Autodesk Fusion 360 part; units mm, degrees
(part 3 of 3)
extrude "Upper ledge pad 189" add sketch "Upper ledge pad 189 outline" along normal blind 2.5 separate body makes body 24 in component "REFERENCE - v11 rubber contact pads"
ref_plane "WorkPlane6" through (0, 0, -2.5) normal (0, 0, 1) x (1, 0, 0) in component "REFERENCE - v11 rubber contact pads"
sketch "Moving shoe rubber pad 189 outline" plane through (0, 0, -2.5) normal (0, 0, 1) x (1, 0, 0) in component "REFERENCE - v11 rubber contact pads"
  line L0 (181, 9.5) -> (197, 9.5)
  line L1 (199, 11.5) -> (199, 23.5)
  line L2 (197, 25.5) -> (181, 25.5)
  line L3 (179, 23.5) -> (179, 11.5)
  arc A0 (197, 9.5) -> (199, 11.5) centre (197, 11.5) ccw
  arc A1 (199, 23.5) -> (197, 25.5) centre (197, 23.5) ccw
  arc A2 (181, 25.5) -> (179, 23.5) centre (181, 23.5) ccw
  arc A3 (179, 11.5) -> (181, 9.5) centre (181, 11.5) ccw
extrude "Moving shoe rubber pad 189" add sketch "Moving shoe rubber pad 189 outline" along normal blind 2.5 separate body makes body 25 in component "REFERENCE - v11 rubber contact pads"
ref_plane "WorkPlane1" through (0, 0, -40) normal (0, 0, 1) x (1, 0, 0) in component "REFERENCE - M5 x 30 DIN 933 clamp bolts"
sketch "M5 hex head 25 outline" plane through (0, 0, -40) normal (0, 0, 1) x (1, 0, 0) in component "REFERENCE - M5 x 30 DIN 933 clamp bolts"
  line L0 (29.6188, 17.5) -> (27.3094, 21.5)
  line L1 (27.3094, 21.5) -> (22.6906, 21.5)
  line L2 (22.6906, 21.5) -> (20.3812, 17.5)
  line L3 (20.3812, 17.5) -> (22.6906, 13.5)
  line L4 (22.6906, 13.5) -> (27.3094, 13.5)
  line L5 (27.3094, 13.5) -> (29.6188, 17.5)
extrude "M5 hex head 25" add sketch "M5 hex head 25 outline" along normal blind 3.5 separate body makes body 26 in component "REFERENCE - M5 x 30 DIN 933 clamp bolts"
ref_plane "WorkPlane2" through (0, 0, -36.5) normal (0, 0, 1) x (1, 0, 0) in component "REFERENCE - M5 x 30 DIN 933 clamp bolts"
sketch "M5 full-thread envelope 25 layout" plane through (0, 0, -36.5) normal (0, 0, 1) x (1, 0, 0) in component "REFERENCE - M5 x 30 DIN 933 clamp bolts"
  circle A0 centre (25, 17.5) radius 2.5
extrude "M5 full-thread envelope 25" add sketch "M5 full-thread envelope 25 layout" along normal blind 30 bodies 26 in component "REFERENCE - M5 x 30 DIN 933 clamp bolts"
ref_plane "WorkPlane1" through (0, 0, -23.7) normal (0, 0, 1) x (1, 0, 0) in component "REFERENCE - M5 DIN 934 captive nuts"
sketch "M5 nut 25 outline" plane through (0, 0, -23.7) normal (0, 0, 1) x (1, 0, 0) in component "REFERENCE - M5 DIN 934 captive nuts"
  line L0 (29.6188, 17.5) -> (27.3094, 21.5)
  line L1 (27.3094, 21.5) -> (22.6906, 21.5)
  line L2 (22.6906, 21.5) -> (20.3812, 17.5)
  line L3 (20.3812, 17.5) -> (22.6906, 13.5)
  line L4 (22.6906, 13.5) -> (27.3094, 13.5)
  line L5 (27.3094, 13.5) -> (29.6188, 17.5)
extrude "M5 nut 25" add sketch "M5 nut 25 outline" along normal blind 4 separate body makes body 27 in component "REFERENCE - M5 DIN 934 captive nuts"
ref_plane "WorkPlane2" through (0, 0, -23.8) normal (0, 0, 1) x (1, 0, 0) in component "REFERENCE - M5 DIN 934 captive nuts"
sketch "M5 thread clearance envelope 25 layout" plane through (0, 0, -23.8) normal (0, 0, 1) x (1, 0, 0) in component "REFERENCE - M5 DIN 934 captive nuts"
  circle A0 centre (25, 17.5) radius 2.6
extrude "M5 thread clearance envelope 25" cut sketch "M5 thread clearance envelope 25 layout" along normal blind 4.2 bodies 27 in component "REFERENCE - M5 DIN 934 captive nuts"
ref_plane "WorkPlane3" through (0, 0, -40) normal (0, 0, 1) x (1, 0, 0) in component "REFERENCE - M5 x 30 DIN 933 clamp bolts"
sketch "M5 hex head 189 outline" plane through (0, 0, -40) normal (0, 0, 1) x (1, 0, 0) in component "REFERENCE - M5 x 30 DIN 933 clamp bolts"
  line L0 (193.6188, 17.5) -> (191.3094, 21.5)
  line L1 (191.3094, 21.5) -> (186.6906, 21.5)
  line L2 (186.6906, 21.5) -> (184.3812, 17.5)
  line L3 (184.3812, 17.5) -> (186.6906, 13.5)
  line L4 (186.6906, 13.5) -> (191.3094, 13.5)
  line L5 (191.3094, 13.5) -> (193.6188, 17.5)
extrude "M5 hex head 189" add sketch "M5 hex head 189 outline" along normal blind 3.5 separate body makes body 28 in component "REFERENCE - M5 x 30 DIN 933 clamp bolts"
ref_plane "WorkPlane4" through (0, 0, -36.5) normal (0, 0, 1) x (1, 0, 0) in component "REFERENCE - M5 x 30 DIN 933 clamp bolts"
sketch "M5 full-thread envelope 189 layout" plane through (0, 0, -36.5) normal (0, 0, 1) x (1, 0, 0) in component "REFERENCE - M5 x 30 DIN 933 clamp bolts"
  circle A0 centre (189, 17.5) radius 2.5
extrude "M5 full-thread envelope 189" add sketch "M5 full-thread envelope 189 layout" along normal blind 30 bodies 28 in component "REFERENCE - M5 x 30 DIN 933 clamp bolts"
ref_plane "WorkPlane3" through (0, 0, -23.7) normal (0, 0, 1) x (1, 0, 0) in component "REFERENCE - M5 DIN 934 captive nuts"
sketch "M5 nut 189 outline" plane through (0, 0, -23.7) normal (0, 0, 1) x (1, 0, 0) in component "REFERENCE - M5 DIN 934 captive nuts"
  line L0 (193.6188, 17.5) -> (191.3094, 21.5)
  line L1 (191.3094, 21.5) -> (186.6906, 21.5)
  line L2 (186.6906, 21.5) -> (184.3812, 17.5)
  line L3 (184.3812, 17.5) -> (186.6906, 13.5)
  line L4 (186.6906, 13.5) -> (191.3094, 13.5)
  line L5 (191.3094, 13.5) -> (193.6188, 17.5)
extrude "M5 nut 189" add sketch "M5 nut 189 outline" along normal blind 4 separate body makes body 29 in component "REFERENCE - M5 DIN 934 captive nuts"
ref_plane "WorkPlane4" through (0, 0, -23.8) normal (0, 0, 1) x (1, 0, 0) in component "REFERENCE - M5 DIN 934 captive nuts"
sketch "M5 thread clearance envelope 189 layout" plane through (0, 0, -23.8) normal (0, 0, 1) x (1, 0, 0) in component "REFERENCE - M5 DIN 934 captive nuts"
  circle A0 centre (189, 17.5) radius 2.6
extrude "M5 thread clearance envelope 189" cut sketch "M5 thread clearance envelope 189 layout" along normal blind 4.2 bodies 27 29 in component "REFERENCE - M5 DIN 934 captive nuts"
ref_plane "WorkPlane1" through (0, 0, 80.4) normal (0, 0, 1) x (1, 0, 0) in component "REFERENCE - six M3 x 10 button screws and washers"
sketch "M3 button head envelope (18, 16) layout" plane through (0, 0, 80.4) normal (0, 0, 1) x (1, 0, 0) in component "REFERENCE - six M3 x 10 button screws and washers"
  circle A0 centre (18, 16) radius 2.85
extrude "M3 button head envelope (18, 16)" add sketch "M3 button head envelope (18, 16) layout" along normal blind 1.65 separate body makes body 30 in component "REFERENCE - six M3 x 10 button screws and washers"
ref_plane "WorkPlane2" through (0, 0, 70.4) normal (0, 0, 1) x (1, 0, 0) in component "REFERENCE - six M3 x 10 button screws and washers"
sketch "M3 screw shaft (18, 16) layout" plane through (0, 0, 70.4) normal (0, 0, 1) x (1, 0, 0) in component "REFERENCE - six M3 x 10 button screws and washers"
  circle A0 centre (18, 16) radius 1.5
extrude "M3 screw shaft (18, 16)" add sketch "M3 screw shaft (18, 16) layout" along normal blind 10 bodies 30 in component "REFERENCE - six M3 x 10 button screws and washers"
ref_plane "WorkPlane3" through (0, 0, 79.9) normal (0, 0, 1) x (1, 0, 0) in component "REFERENCE - six M3 x 10 button screws and washers"
sketch "M3 washer OD (18, 16) layout" plane through (0, 0, 79.9) normal (0, 0, 1) x (1, 0, 0) in component "REFERENCE - six M3 x 10 button screws and washers"
  circle A0 centre (18, 16) radius 3.5
extrude "M3 washer OD (18, 16)" add sketch "M3 washer OD (18, 16) layout" along normal blind 0.5 bodies 30 in component "REFERENCE - six M3 x 10 button screws and washers"
ref_plane "WorkPlane1" through (0, 0, 71.1) normal (0, 0, 1) x (1, 0, 0) in component "REFERENCE - six M3 DIN 934 nuts"
sketch "M3 nut (18, 16) outline" plane through (0, 0, 71.1) normal (0, 0, 1) x (1, 0, 0) in component "REFERENCE - six M3 DIN 934 nuts"
  line L0 (21.1754, 16) -> (19.5877, 18.75)
  line L1 (19.5877, 18.75) -> (16.4123, 18.75)
  line L2 (16.4123, 18.75) -> (14.8246, 16)
  line L3 (14.8246, 16) -> (16.4123, 13.25)
  line L4 (16.4123, 13.25) -> (19.5877, 13.25)
  line L5 (19.5877, 13.25) -> (21.1754, 16)
extrude "M3 nut (18, 16)" add sketch "M3 nut (18, 16) outline" along normal blind 2.4 separate body makes body 31 in component "REFERENCE - six M3 DIN 934 nuts"
ref_plane "WorkPlane2" through (0, 0, 71) normal (0, 0, 1) x (1, 0, 0) in component "REFERENCE - six M3 DIN 934 nuts"
sketch "M3 thread clearance envelope (18, 16) layout" plane through (0, 0, 71) normal (0, 0, 1) x (1, 0, 0) in component "REFERENCE - six M3 DIN 934 nuts"
  circle A0 centre (18, 16) radius 1.6
extrude "M3 thread clearance envelope (18, 16)" cut sketch "M3 thread clearance envelope (18, 16) layout" along normal blind 2.6 bodies 31 in component "REFERENCE - six M3 DIN 934 nuts"
ref_plane "WorkPlane4" through (0, 0, 80.4) normal (0, 0, 1) x (1, 0, 0) in component "REFERENCE - six M3 x 10 button screws and washers"
sketch "M3 button head envelope (32, 16) layout" plane through (0, 0, 80.4) normal (0, 0, 1) x (1, 0, 0) in component "REFERENCE - six M3 x 10 button screws and washers"
  circle A0 centre (32, 16) radius 2.85
extrude "M3 button head envelope (32, 16)" add sketch "M3 button head envelope (32, 16) layout" along normal blind 1.65 separate body makes body 32 in component "REFERENCE - six M3 x 10 button screws and washers"
ref_plane "WorkPlane5" through (0, 0, 70.4) normal (0, 0, 1) x (1, 0, 0) in component "REFERENCE - six M3 x 10 button screws and washers"
sketch "M3 screw shaft (32, 16) layout" plane through (0, 0, 70.4) normal (0, 0, 1) x (1, 0, 0) in component "REFERENCE - six M3 x 10 button screws and washers"
  circle A0 centre (32, 16) radius 1.5
extrude "M3 screw shaft (32, 16)" add sketch "M3 screw shaft (32, 16) layout" along normal blind 10 bodies 32 in component "REFERENCE - six M3 x 10 button screws and washers"
ref_plane "WorkPlane6" through (0, 0, 79.9) normal (0, 0, 1) x (1, 0, 0) in component "REFERENCE - six M3 x 10 button screws and washers"
sketch "M3 washer OD (32, 16) layout" plane through (0, 0, 79.9) normal (0, 0, 1) x (1, 0, 0) in component "REFERENCE - six M3 x 10 button screws and washers"
  circle A0 centre (32, 16) radius 3.5
extrude "M3 washer OD (32, 16)" add sketch "M3 washer OD (32, 16) layout" along normal blind 0.5 bodies 32 in component "REFERENCE - six M3 x 10 button screws and washers"
ref_plane "WorkPlane3" through (0, 0, 71.1) normal (0, 0, 1) x (1, 0, 0) in component "REFERENCE - six M3 DIN 934 nuts"
sketch "M3 nut (32, 16) outline" plane through (0, 0, 71.1) normal (0, 0, 1) x (1, 0, 0) in component "REFERENCE - six M3 DIN 934 nuts"
  line L0 (35.1754, 16) -> (33.5877, 18.75)
  line L1 (33.5877, 18.75) -> (30.4123, 18.75)
  line L2 (30.4123, 18.75) -> (28.8246, 16)
  line L3 (28.8246, 16) -> (30.4123, 13.25)
  line L4 (30.4123, 13.25) -> (33.5877, 13.25)
  line L5 (33.5877, 13.25) -> (35.1754, 16)
extrude "M3 nut (32, 16)" add sketch "M3 nut (32, 16) outline" along normal blind 2.4 separate body makes body 33 in component "REFERENCE - six M3 DIN 934 nuts"
ref_plane "WorkPlane4" through (0, 0, 71) normal (0, 0, 1) x (1, 0, 0) in component "REFERENCE - six M3 DIN 934 nuts"
sketch "M3 thread clearance envelope (32, 16) layout" plane through (0, 0, 71) normal (0, 0, 1) x (1, 0, 0) in component "REFERENCE - six M3 DIN 934 nuts"
  circle A0 centre (32, 16) radius 1.6
extrude "M3 thread clearance envelope (32, 16)" cut sketch "M3 thread clearance envelope (32, 16) layout" along normal blind 2.6 bodies 31 33 in component "REFERENCE - six M3 DIN 934 nuts"
ref_plane "WorkPlane7" through (0, 0, 80.4) normal (0, 0, 1) x (1, 0, 0) in component "REFERENCE - six M3 x 10 button screws and washers"
sketch "M3 button head envelope (182, 16) layout" plane through (0, 0, 80.4) normal (0, 0, 1) x (1, 0, 0) in component "REFERENCE - six M3 x 10 button screws and washers"
  circle A0 centre (182, 16) radius 2.85
extrude "M3 button head envelope (182, 16)" add sketch "M3 button head envelope (182, 16) layout" along normal blind 1.65 separate body makes body 34 in component "REFERENCE - six M3 x 10 button screws and washers"
ref_plane "WorkPlane8" through (0, 0, 70.4) normal (0, 0, 1) x (1, 0, 0) in component "REFERENCE - six M3 x 10 button screws and washers"
sketch "M3 screw shaft (182, 16) layout" plane through (0, 0, 70.4) normal (0, 0, 1) x (1, 0, 0) in component "REFERENCE - six M3 x 10 button screws and washers"
  circle A0 centre (182, 16) radius 1.5
extrude "M3 screw shaft (182, 16)" add sketch "M3 screw shaft (182, 16) layout" along normal blind 10 bodies 34 in component "REFERENCE - six M3 x 10 button screws and washers"
ref_plane "WorkPlane9" through (0, 0, 79.9) normal (0, 0, 1) x (1, 0, 0) in component "REFERENCE - six M3 x 10 button screws and washers"
sketch "M3 washer OD (182, 16) layout" plane through (0, 0, 79.9) normal (0, 0, 1) x (1, 0, 0) in component "REFERENCE - six M3 x 10 button screws and washers"
  circle A0 centre (182, 16) radius 3.5
extrude "M3 washer OD (182, 16)" add sketch "M3 washer OD (182, 16) layout" along normal blind 0.5 bodies 34 in component "REFERENCE - six M3 x 10 button screws and washers"
ref_plane "WorkPlane5" through (0, 0, 71.1) normal (0, 0, 1) x (1, 0, 0) in component "REFERENCE - six M3 DIN 934 nuts"
sketch "M3 nut (182, 16) outline" plane through (0, 0, 71.1) normal (0, 0, 1) x (1, 0, 0) in component "REFERENCE - six M3 DIN 934 nuts"
  line L0 (185.1754, 16) -> (183.5877, 18.75)
  line L1 (183.5877, 18.75) -> (180.4123, 18.75)
  line L2 (180.4123, 18.75) -> (178.8246, 16)
  line L3 (178.8246, 16) -> (180.4123, 13.25)
  line L4 (180.4123, 13.25) -> (183.5877, 13.25)
  line L5 (183.5877, 13.25) -> (185.1754, 16)
extrude "M3 nut (182, 16)" add sketch "M3 nut (182, 16) outline" along normal blind 2.4 separate body makes body 35 in component "REFERENCE - six M3 DIN 934 nuts"
ref_plane "WorkPlane6" through (0, 0, 71) normal (0, 0, 1) x (1, 0, 0) in component "REFERENCE - six M3 DIN 934 nuts"
sketch "M3 thread clearance envelope (182, 16) layout" plane through (0, 0, 71) normal (0, 0, 1) x (1, 0, 0) in component "REFERENCE - six M3 DIN 934 nuts"
  circle A0 centre (182, 16) radius 1.6
extrude "M3 thread clearance envelope (182, 16)" cut sketch "M3 thread clearance envelope (182, 16) layout" along normal blind 2.6 bodies 31 33 35 in component "REFERENCE - six M3 DIN 934 nuts"
ref_plane "WorkPlane10" through (0, 0, 80.4) normal (0, 0, 1) x (1, 0, 0) in component "REFERENCE - six M3 x 10 button screws and washers"
sketch "M3 button head envelope (196, 16) layout" plane through (0, 0, 80.4) normal (0, 0, 1) x (1, 0, 0) in component "REFERENCE - six M3 x 10 button screws and washers"
  circle A0 centre (196, 16) radius 2.85
extrude "M3 button head envelope (196, 16)" add sketch "M3 button head envelope (196, 16) layout" along normal blind 1.65 separate body makes body 36 in component "REFERENCE - six M3 x 10 button screws and washers"
ref_plane "WorkPlane11" through (0, 0, 70.4) normal (0, 0, 1) x (1, 0, 0) in component "REFERENCE - six M3 x 10 button screws and washers"
sketch "M3 screw shaft (196, 16) layout" plane through (0, 0, 70.4) normal (0, 0, 1) x (1, 0, 0) in component "REFERENCE - six M3 x 10 button screws and washers"
  circle A0 centre (196, 16) radius 1.5
extrude "M3 screw shaft (196, 16)" add sketch "M3 screw shaft (196, 16) layout" along normal blind 10 bodies 36 in component "REFERENCE - six M3 x 10 button screws and washers"
ref_plane "WorkPlane12" through (0, 0, 79.9) normal (0, 0, 1) x (1, 0, 0) in component "REFERENCE - six M3 x 10 button screws and washers"
sketch "M3 washer OD (196, 16) layout" plane through (0, 0, 79.9) normal (0, 0, 1) x (1, 0, 0) in component "REFERENCE - six M3 x 10 button screws and washers"
  circle A0 centre (196, 16) radius 3.5
extrude "M3 washer OD (196, 16)" add sketch "M3 washer OD (196, 16) layout" along normal blind 0.5 bodies 36 in component "REFERENCE - six M3 x 10 button screws and washers"
ref_plane "WorkPlane7" through (0, 0, 71.1) normal (0, 0, 1) x (1, 0, 0) in component "REFERENCE - six M3 DIN 934 nuts"
sketch "M3 nut (196, 16) outline" plane through (0, 0, 71.1) normal (0, 0, 1) x (1, 0, 0) in component "REFERENCE - six M3 DIN 934 nuts"
  line L0 (199.1754, 16) -> (197.5877, 18.75)
  line L1 (197.5877, 18.75) -> (194.4123, 18.75)
  line L2 (194.4123, 18.75) -> (192.8246, 16)
  line L3 (192.8246, 16) -> (194.4123, 13.25)
  line L4 (194.4123, 13.25) -> (197.5877, 13.25)
  line L5 (197.5877, 13.25) -> (199.1754, 16)
extrude "M3 nut (196, 16)" add sketch "M3 nut (196, 16) outline" along normal blind 2.4 separate body makes body 37 in component "REFERENCE - six M3 DIN 934 nuts"
ref_plane "WorkPlane8" through (0, 0, 71) normal (0, 0, 1) x (1, 0, 0) in component "REFERENCE - six M3 DIN 934 nuts"
sketch "M3 thread clearance envelope (196, 16) layout" plane through (0, 0, 71) normal (0, 0, 1) x (1, 0, 0) in component "REFERENCE - six M3 DIN 934 nuts"
  circle A0 centre (196, 16) radius 1.6
extrude "M3 thread clearance envelope (196, 16)" cut sketch "M3 thread clearance envelope (196, 16) layout" along normal blind 2.6 bodies 31 33 35 37 in component "REFERENCE - six M3 DIN 934 nuts"
ref_plane "WorkPlane13" through (0, 0, 80.4) normal (0, 0, 1) x (1, 0, 0) in component "REFERENCE - six M3 x 10 button screws and washers"
sketch "M3 button head envelope (92, -2.5) layout" plane through (0, 0, 80.4) normal (0, 0, 1) x (1, 0, 0) in component "REFERENCE - six M3 x 10 button screws and washers"
  circle A0 centre (92, -2.5) radius 2.85
extrude "M3 button head envelope (92, -2.5)" add sketch "M3 button head envelope (92, -2.5) layout" along normal blind 1.65 separate body makes body 38 in component "REFERENCE - six M3 x 10 button screws and washers"
ref_plane "WorkPlane14" through (0, 0, 70.4) normal (0, 0, 1) x (1, 0, 0) in component "REFERENCE - six M3 x 10 button screws and washers"
sketch "M3 screw shaft (92, -2.5) layout" plane through (0, 0, 70.4) normal (0, 0, 1) x (1, 0, 0) in component "REFERENCE - six M3 x 10 button screws and washers"
  circle A0 centre (92, -2.5) radius 1.5
extrude "M3 screw shaft (92, -2.5)" add sketch "M3 screw shaft (92, -2.5) layout" along normal blind 10 bodies 38 in component "REFERENCE - six M3 x 10 button screws and washers"
ref_plane "WorkPlane15" through (0, 0, 79.9) normal (0, 0, 1) x (1, 0, 0) in component "REFERENCE - six M3 x 10 button screws and washers"
sketch "M3 washer OD (92, -2.5) layout" plane through (0, 0, 79.9) normal (0, 0, 1) x (1, 0, 0) in component "REFERENCE - six M3 x 10 button screws and washers"
  circle A0 centre (92, -2.5) radius 3.5
extrude "M3 washer OD (92, -2.5)" add sketch "M3 washer OD (92, -2.5) layout" along normal blind 0.5 bodies 38 in component "REFERENCE - six M3 x 10 button screws and washers"
ref_plane "WorkPlane9" through (0, 0, 71.1) normal (0, 0, 1) x (1, 0, 0) in component "REFERENCE - six M3 DIN 934 nuts"
sketch "M3 nut (92, -2.5) outline" plane through (0, 0, 71.1) normal (0, 0, 1) x (1, 0, 0) in component "REFERENCE - six M3 DIN 934 nuts"
  line L0 (95.1754, -2.5) -> (93.5877, 0.25)
  line L1 (93.5877, 0.25) -> (90.4123, 0.25)
  line L2 (90.4123, 0.25) -> (88.8246, -2.5)
  line L3 (88.8246, -2.5) -> (90.4123, -5.25)
  line L4 (90.4123, -5.25) -> (93.5877, -5.25)
  line L5 (93.5877, -5.25) -> (95.1754, -2.5)
extrude "M3 nut (92, -2.5)" add sketch "M3 nut (92, -2.5) outline" along normal blind 2.4 separate body makes body 39 in component "REFERENCE - six M3 DIN 934 nuts"
ref_plane "WorkPlane10" through (0, 0, 71) normal (0, 0, 1) x (1, 0, 0) in component "REFERENCE - six M3 DIN 934 nuts"
sketch "M3 thread clearance envelope (92, -2.5) layout" plane through (0, 0, 71) normal (0, 0, 1) x (1, 0, 0) in component "REFERENCE - six M3 DIN 934 nuts"
  circle A0 centre (92, -2.5) radius 1.6
extrude "M3 thread clearance envelope (92, -2.5)" cut sketch "M3 thread clearance envelope (92, -2.5) layout" along normal blind 2.6 bodies 31 33 35 37 39 in component "REFERENCE - six M3 DIN 934 nuts"
ref_plane "WorkPlane16" through (0, 0, 80.4) normal (0, 0, 1) x (1, 0, 0) in component "REFERENCE - six M3 x 10 button screws and washers"
sketch "M3 button head envelope (122, -2.5) layout" plane through (0, 0, 80.4) normal (0, 0, 1) x (1, 0, 0) in component "REFERENCE - six M3 x 10 button screws and washers"
  circle A0 centre (122, -2.5) radius 2.85
extrude "M3 button head envelope (122, -2.5)" add sketch "M3 button head envelope (122, -2.5) layout" along normal blind 1.65 separate body makes body 40 in component "REFERENCE - six M3 x 10 button screws and washers"
ref_plane "WorkPlane17" through (0, 0, 70.4) normal (0, 0, 1) x (1, 0, 0) in component "REFERENCE - six M3 x 10 button screws and washers"
sketch "M3 screw shaft (122, -2.5) layout" plane through (0, 0, 70.4) normal (0, 0, 1) x (1, 0, 0) in component "REFERENCE - six M3 x 10 button screws and washers"
  circle A0 centre (122, -2.5) radius 1.5
extrude "M3 screw shaft (122, -2.5)" add sketch "M3 screw shaft (122, -2.5) layout" along normal blind 10 bodies 40 in component "REFERENCE - six M3 x 10 button screws and washers"
ref_plane "WorkPlane18" through (0, 0, 79.9) normal (0, 0, 1) x (1, 0, 0) in component "REFERENCE - six M3 x 10 button screws and washers"
sketch "M3 washer OD (122, -2.5) layout" plane through (0, 0, 79.9) normal (0, 0, 1) x (1, 0, 0) in component "REFERENCE - six M3 x 10 button screws and washers"
  circle A0 centre (122, -2.5) radius 3.5
extrude "M3 washer OD (122, -2.5)" add sketch "M3 washer OD (122, -2.5) layout" along normal blind 0.5 bodies 40 in component "REFERENCE - six M3 x 10 button screws and washers"
ref_plane "WorkPlane11" through (0, 0, 71.1) normal (0, 0, 1) x (1, 0, 0) in component "REFERENCE - six M3 DIN 934 nuts"
sketch "M3 nut (122, -2.5) outline" plane through (0, 0, 71.1) normal (0, 0, 1) x (1, 0, 0) in component "REFERENCE - six M3 DIN 934 nuts"
  line L0 (125.1754, -2.5) -> (123.5877, 0.25)
  line L1 (123.5877, 0.25) -> (120.4123, 0.25)
  line L2 (120.4123, 0.25) -> (118.8246, -2.5)
  line L3 (118.8246, -2.5) -> (120.4123, -5.25)
  line L4 (120.4123, -5.25) -> (123.5877, -5.25)
  line L5 (123.5877, -5.25) -> (125.1754, -2.5)
extrude "M3 nut (122, -2.5)" add sketch "M3 nut (122, -2.5) outline" along normal blind 2.4 separate body makes body 41 in component "REFERENCE - six M3 DIN 934 nuts"
ref_plane "WorkPlane12" through (0, 0, 71) normal (0, 0, 1) x (1, 0, 0) in component "REFERENCE - six M3 DIN 934 nuts"
sketch "M3 thread clearance envelope (122, -2.5) layout" plane through (0, 0, 71) normal (0, 0, 1) x (1, 0, 0) in component "REFERENCE - six M3 DIN 934 nuts"
  circle A0 centre (122, -2.5) radius 1.6
extrude "M3 thread clearance envelope (122, -2.5)" cut sketch "M3 thread clearance envelope (122, -2.5) layout" along normal blind 2.6 bodies 31 33 35 37 39 41 in component "REFERENCE - six M3 DIN 934 nuts"
ref_plane "WorkPlane1" through (99, 0, 0) normal (1, 0, 0) x (0, 1, 0) in component "REFERENCE - v11 ribbon 16 x 0.35 mm assumed"
sketch "Illustrative ribbon clearance outline" plane through (99, 0, 0) normal (1, 0, 0) x (0, 0, -1) in component "REFERENCE - v11 ribbon 16 x 0.35 mm assumed"
  line L0 (13, -17.675) -> (8.9063, -17.675)
  line L1 (8.9063, -17.675) -> (6.825, -14.553)
  line L2 (6.825, -14.553) -> (6.825, -13.0967)
  line L3 (6.825, -13.0967) -> (3.4496, -10.975)
  line L4 (3.4496, -10.975) -> (-81.5, -10.975)
  line L5 (-81.5, -10.975) -> (-81.5, -10.625)
  line L6 (-81.5, -10.625) -> (3.5504, -10.625)
  line L7 (3.5504, -10.625) -> (7.175, -12.9033)
  line L8 (7.175, -12.9033) -> (7.175, -14.447)
  line L9 (7.175, -14.447) -> (9.0937, -17.325)
  line L10 (9.0937, -17.325) -> (13, -17.325)
  line L11 (13, -17.325) -> (13, -17.675)
extrude "Illustrative ribbon clearance" add sketch "Illustrative ribbon clearance outline" along normal blind 16 separate body makes body 42 in component "REFERENCE - v11 ribbon 16 x 0.35 mm assumed"
component "REFERENCE - INIU P51L-E2 115 x 73 x 29 mm" placed x (-1, 0, 0) y (0, 0, 1) z (0, 1, 0) at (129, -14, 77)
component "REFERENCE - Raspberry Pi4 rotated ports" placed x (0, 0, -1) y (1, 0, 0) z (0, -1, 0) at (131, 60, 174.5)
component "REFERENCE - Waveshare RPi Camera G PCB and lens" placed x (-1, 0, 0) y (0, 1, 0) z (0, 0, -1) at (126, -21.65, -8)
component "REFERENCE - upward-stepped frame - back wall assumed" placed x (1, 0, 0) y (0, 1, 0) z (0, 0, 1) at (0, 0, 0)
component "01 Electronics case - PRINT 1" placed x (1, 0, 0) y (0, 1, 0) z (0, 0, 1) at (0, 0, 8.5)
component "02 Flat front and ribbon cover - PRINT 1" placed x (1, 0, 0) y (0, 1, 0) z (0, 0, 1) at (0, 0, 8.5)
component "03 Camera guard with corner bumpers - PRINT 1" placed x (1, 0, 0) y (0, 1, 0) z (0, 0, 1) at (0, 0, 0)
component "04 Downward camera carrier - PRINT 1" placed x (1, 0, 0) y (0, 1, 0) z (0, 0, 1) at (0, 0, 0)
component "05 Adjustable C clamp - PRINT 2" placed x (1, 0, 0) y (0, 1, 0) z (0, 0, 1) at (25, 0, 0)
component "06 Padded pressure shoe - PRINT 2" placed x (1, 0, 0) y (0, 1, 0) z (0, 0, 1) at (25, 0, 0)
component "07 M5 hex bolt hand knob - PRINT 2" placed x (1, 0, 0) y (0, 1, 0) z (0, 0, 1) at (25, 0, 0)
component "05 Adjustable C clamp - PRINT 2" placed x (1, 0, 0) y (0, 1, 0) z (0, 0, 1) at (189, 0, 0)
component "06 Padded pressure shoe - PRINT 2" placed x (1, 0, 0) y (0, 1, 0) z (0, 0, 1) at (189, 0, 0)
component "07 M5 hex bolt hand knob - PRINT 2" placed x (1, 0, 0) y (0, 1, 0) z (0, 0, 1) at (189, 0, 0)
component "REFERENCE - v11 rubber contact pads" placed x (1, 0, 0) y (0, 1, 0) z (0, 0, 1) at (0, 0, 0)
component "REFERENCE - M5 x 30 DIN 933 clamp bolts" placed x (1, 0, 0) y (0, 1, 0) z (0, 0, 1) at (0, 0, 0)
component "REFERENCE - M5 DIN 934 captive nuts" placed x (1, 0, 0) y (0, 1, 0) z (0, 0, 1) at (0, 0, 0)
component "REFERENCE - six M3 x 10 button screws and washers" placed x (1, 0, 0) y (0, 1, 0) z (0, 0, 1) at (0, 0, 0)
component "REFERENCE - six M3 DIN 934 nuts" placed x (1, 0, 0) y (0, 1, 0) z (0, 0, 1) at (0, 0, 0)
component "REFERENCE - v11 ribbon 16 x 0.35 mm assumed" placed x (1, 0, 0) y (0, 1, 0) z (0, 0, 1) at (0, 0, 0)
equation "wall = 2.4 mm" comment "Printed shell wall and tray thickness"
equation "battery_tray_height = 37 mm" comment "Battery chamber outside height"
equation "upper_height = 32 mm" comment "Pi chamber height above battery tray"
equation "lid_thickness = 2.4 mm" comment "Removable lid"
equation "pi_standoff_height = 5 mm" comment "Pi underside clearance"
equation "pad_recess_depth = 0.8 mm" comment "Use 3 mm rubber pads; 2.2 mm projects below case"
equation "camera_carrier_thickness = 3 mm" comment "Camera backplate"
equation "camera_standoff_height = 2.5 mm" comment "Clearance under camera PCB"
equation "camera_lens_opening = 22 mm" comment "Generous opening; check actual lens barrel before final print"
equation "camera_cap_height = 17 mm" comment "Cap height above carrier; lens must project beyond the front"
equation "snap_clearance = 0.35 mm" comment "Nominal printed locator clearance; fit-test before assembly"
equation "pi_screw_pilot = 2.1 mm" comment "Provisional PETG pilot. Fit-test with actual screws before the full print."
equation "d893 = pi_screw_pilot"
equation "d894 = pi_screw_pilot"
equation "d895 = pi_screw_pilot"
equation "d896 = pi_screw_pilot"
equation "camera_screw_pilot = 1.7 mm" comment "Provisional PETG pilot. Fit-test with actual screws before the full print."
equation "d898 = camera_screw_pilot"
equation "d899 = camera_screw_pilot"
equation "d900 = camera_screw_pilot"
equation "d901 = camera_screw_pilot"
equation "v11_clamp_web = 10 mm" comment "YZ profile web; print broad X face down; rebuild geometry through script to change layout"
equation "v11_clamp_jaw = 12 mm" comment "Lower jaw thickness; rebuild geometry through script to change layout"
equation "v11_upper_jaw = 8 mm" comment "Upper ledge thickness; rebuild geometry through script to change layout"
equation "v11_case_raise = 8.5 mm" comment "Electronics elevation above v10; rebuild geometry through script to change layout"
named bodies: "INIU envelope - check supplied cable position", "Pi PCB 85 x 56 x 1.6", "USB3", "USB2", "Ethernet", "USB-C", "HDMI0", "HDMI1", "Audio", "Camera PCB 25 x 24", "Open-front case", "Front cover", "Camera guard shell", "Camera spine", "Pressure spreader", "Lower ledge pad 25", "Upper ledge pad 25", "Moving shoe rubber pad 25", "Lower ledge pad 189", "Upper ledge pad 189", "Moving shoe rubber pad 189"
